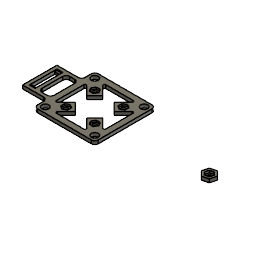
Assembly (1) (Autodesk Fusion 360 archive; units mm, degrees)
design "cam base (1)"
part number: 2026-03-15-12-51-07-522
Autodesk Fusion 360 part; units mm, degrees
sketch "Sketch1" plane through (0, 0, 0) normal (0, 1, 0) x (1, 0, 0)
  line L0 (26.5, -26.5) -> (-26.5, -26.5)
  line L1 (-26.5, -26.5) -> (-26.5, 26.5)
  line L2 (-26.5, 26.5) -> (26.5, 26.5)
  line L3 (26.5, 26.5) -> (26.5, -26.5)
  line L4 (26.5, -26.5) -> (-26.5, 26.5) construction
  line L5 (-26.5, -26.5) -> (26.5, 26.5) construction
  circle A0 centre (-21.5503, 21.5503) radius 3
  circle A1 centre (-21.5503, -21.5503) radius 3
  circle A2 centre (21.5503, -21.5503) radius 3
  circle A3 centre (21.5503, 21.5503) radius 3
  line L6 (-40, -12) -> (-45, -12)
  line L7 (-45, -12) -> (-45, 12)
  line L8 (-45, 12) -> (-40, 12)
  line L9 (-40, 12) -> (-40, -12)
  line L10 (-40, -12) -> (-45, 12) construction
  line L11 (-45, -12) -> (-40, 12) construction
  line L12 (-45, -10) -> (-40, -10)
  line L13 (-45, 10) -> (-40, 10)
  line L14 (17.9645, -17.9645) -> (21.5, -14.4289)
  line L15 (17.9645, 17.9645) -> (21.5, 14.4289)
  line L16 (21.5, 14.4289) -> (21.5, -14.4289)
  line L17 (21.5, -14.4289) -> (14.4289, -21.5)
  line L18 (21.5, 14.4289) -> (14.4289, 21.5)
  line L19 (-21.5, -14.4289) -> (-14.4289, -21.5)
  line L20 (-21.5, 14.4289) -> (-21.5, -14.4289)
  line L21 (-21.5, 14.4289) -> (-14.4289, 21.5)
  line L22 (14.4289, -21.5) -> (-14.4289, -21.5)
  line L23 (-14.4289, 21.5) -> (14.4289, 21.5)
  line L24 (-37, 15) -> (-37, -15)
  line L25 (-37, -15) -> (-48, -15)
  line L26 (-48, -15) -> (-48, 15)
  line L27 (-48, 15) -> (-37, 15)
  line L28 (-37, -15) -> (-26.5, -15)
  line L29 (-37, 15) -> (-26.5, 15)
  line L30 (-37, -12) -> (-26.5, -12)
  line L31 (-37, 12) -> (-26.5, 12)
  line L32 (-12.5, 12.5) -> (12.5, 12.5)
  line L33 (12.5, 12.5) -> (12.5, -12.5)
  line L34 (12.5, -12.5) -> (-12.5, -12.5)
  line L35 (-12.5, -12.5) -> (-12.5, 12.5)
  line L36 (-12.5, 12.5) -> (12.5, -12.5) construction
  line L37 (12.5, 12.5) -> (-12.5, -12.5) construction
  line L38 (9.499, 14.3011) -> (9.4397, 10.8016)
  line L39 (9.4397, 10.8016) -> (12.4407, 9.0005)
  line L40 (12.4407, 9.0005) -> (15.501, 10.6989)
  line L41 (15.501, 10.6989) -> (15.5603, 14.1984)
  line L42 (15.5603, 14.1984) -> (12.5593, 15.9995)
  line L43 (12.5593, 15.9995) -> (9.499, 14.3011)
  line L44 (-10.8016, 9.4397) -> (-9.0005, 12.4407)
  line L45 (-9.0005, 12.4407) -> (-10.6989, 15.501)
  line L46 (-10.6989, 15.501) -> (-14.1984, 15.5603)
  line L47 (-14.1984, 15.5603) -> (-15.9995, 12.5593)
  line L48 (-15.9995, 12.5593) -> (-14.3011, 9.499)
  line L49 (-14.3011, 9.499) -> (-10.8016, 9.4397)
  line L50 (-9.4397, -10.8016) -> (-12.4407, -9.0005)
  line L51 (-12.4407, -9.0005) -> (-15.501, -10.6989)
  line L52 (-15.501, -10.6989) -> (-15.5603, -14.1984)
  line L53 (-15.5603, -14.1984) -> (-12.5593, -15.9995)
  line L54 (-12.5593, -15.9995) -> (-9.499, -14.3011)
  line L55 (-9.499, -14.3011) -> (-9.4397, -10.8016)
  line L56 (10.8016, -9.4397) -> (9.0005, -12.4407)
  line L57 (9.0005, -12.4407) -> (10.6989, -15.501)
  line L58 (10.6989, -15.501) -> (14.1984, -15.5603)
  line L59 (14.1984, -15.5603) -> (15.9995, -12.5593)
  line L60 (15.9995, -12.5593) -> (14.3011, -9.499)
  line L61 (14.3011, -9.499) -> (10.8016, -9.4397)
  circle A4 centre (12.5, 12.5) radius 1.75
  circle A5 centre (-12.5, 12.5) radius 1.75
  circle A6 centre (-12.5, -12.5) radius 1.75
  circle A7 centre (12.5, -12.5) radius 1.75
  line L62 (21.5, 14.4289) -> (11.9541, 4.883)
  line L63 (14.4289, 21.5) -> (4.883, 11.9541)
  line L64 (4.883, 11.9541) -> (11.9541, 4.883)
  line L65 (-21.5, 14.4289) -> (-11.9541, 4.883)
  line L66 (-11.9541, 4.883) -> (-4.883, 11.9541)
  line L67 (-14.4289, 21.5) -> (-4.883, 11.9541)
  line L68 (-14.4289, -21.5) -> (-4.883, -11.9541)
  line L69 (-4.883, -11.9541) -> (-11.9541, -4.883)
  line L70 (-21.5, -14.4289) -> (-11.9541, -4.883)
  line L71 (21.5, -14.4289) -> (11.9541, -4.883)
  line L72 (11.9541, -4.883) -> (4.883, -11.9541)
  line L73 (14.4289, -21.5) -> (4.883, -11.9541)
  point P0 (-42.5, 0)
  point P1 (-42.5, 0)
  point P2 (12.5, 12.5)
  dimension "d1" = 53
  dimension "d2" = 53
  dimension "d3" = 6
  dimension "d5" = 360
  dimension "d8" = 5
  dimension "d9" = 24
  dimension "d11" = 2
  dimension "d12" = 2
  dimension "d20" = 7
  dimension "d21" = 5
  dimension "d22" = 5
  dimension "d24" = 5
  dimension "d27" = 10
  dimension "d33" = 5
  dimension "d34" = 5
  dimension "d35" = 5
  dimension "d39" = 5
  dimension "d40" = 5
  dimension "d41" = 5
  dimension "d42" = 10
  dimension "d43" = 10
  dimension "d44" = 40
  dimension "d47" = -3
  dimension "d54" = 25
  dimension "d55" = 25
  dimension "d56" = 3.5
  dimension "d58" = 360
  dimension "d59" = 3.5
  dimension "d61" = 360
  dimension "d69" = 13.5
  dimension "d70" = 13.5
  dimension "d72" = 360
  constraint horizontal L0
  constraint perpendicular L0 L1
  constraint parallel L0 L2
  constraint parallel L1 L3
  constraint coincident L4 origin
  constraint coincident L5 origin
  constraint coincident L4 A0.centre
  constraint horizontal L6
  constraint perpendicular L6 L7
  constraint parallel L6 L8
  constraint parallel L7 L9
  constraint coincident L10 P1
  constraint coincident L11 P1
  constraint coincident P1 P0
  constraint coincident L7 L12.start
  constraint coincident L9 L12.end
  constraint perpendicular L9 L12
  constraint coincident L7 L13.start
  constraint coincident L9 L13.end
  constraint perpendicular L9 L13
  constraint perpendicular L4 L14
  constraint perpendicular L5 L15
  constraint perpendicular L4 L17
  constraint perpendicular L5 L18
  constraint horizontal L22
  constraint parallel L22 L23
  constraint coincident L1 L28.end
  constraint perpendicular L1 L28
  constraint coincident L1 L29.end
  constraint perpendicular L1 L29
  constraint coincident L24 L30.start
  constraint coincident L1 L30.end
  constraint perpendicular L1 L30
  constraint coincident L24 L31.start
  constraint coincident L1 L31.end
  constraint perpendicular L1 L31
  constraint horizontal L32
  constraint perpendicular L32 L33
  constraint parallel L32 L34
  constraint parallel L33 L35
  constraint coincident L36 origin
  constraint coincident L37 origin
  constraint coincident P2 L32.end
  constraint perpendicular L18 L62
  constraint perpendicular L18 L63
  measures "d1" distance of L1.end L2.end
  measures "d2" distance of L0.end L1.end
  measures "d3" diameter of A0
  measures "d8" distance of L7.end L8.end
  measures "d9" distance of L6.end L7.end
  measures "d11" distance of L6 L12
  measures "d12" distance of L8 L13
  measures "d20" distance of L1.end A0.centre
  measures "d21" distance of L14.start L14.end
  measures "d22" distance of L15.start L15.end
  measures "d24" distance of L3 L16
  measures "d27" distance of L15.end L18.end
  measures "d33" distance of L1 L20
  measures "d34" distance of L0 L22
  measures "d35" distance of L2 L23
  measures "d39" distance of L4 L17.end
  measures "d40" distance of L5 L19.end
  measures "d41" distance of L4 L21.end
  measures "d42" distance of L20.start L21.end
  measures "d43" distance of L19.end L19.start
  measures "d44" distance of origin L9
  measures "d54" distance of L33.end L34.end
  measures "d55" distance of P2 L33.end
  measures "d56" distance of L38.start P2
  measures "d59" diameter of A4
  measures "d69" distance of L15.end L62.end
  measures "d70" distance of L18.end L63.end
extrude "Extrude1" add sketch "Sketch1" along normal blind 3 contours L0 L1 L2 L3 | L1 L24 L28 L30 | L24 L25 L26 L27 | L1 L24 L29 L31 | L14 L17 L33 L34 L57 L58 L59 L60 L61 L71 L73 | L15 L18 L32 L33 L38 L40 L41 L42 L43 L62 L63 | L33 L34 L56 L57 L61 L71 L72 L73 | L19 L34 L35 L51 L52 L53 L54 L55 L68 L70 | L32 L33 L38 L39 L40 L62 L63 L64 | L34 L35 L50 L51 L55 L68 L69 L70 | L21 L32 L35 L45 L46 L47 L48 L49 L65 L67 | L32 L35 L44 L45 L49 L65 L66 L67 makes body 1
extrude "Extrude2" add sketch "Sketch1" along normal blind 2 separate body contours L6 L7 L9 L12 | L7 L8 L9 L13 makes body 2 at (-41.6667, 0.6667, 12) makes body 3 at (-41.6667, 0, -10.6667)
combine "Combine1" operation add target body 1 tool bodies 3 2
fillet "Fillet2" radius 3 4 edges at (-37, 1.5, 12) (-37, 1.5, -12) (-26.5, 1.5, 12) (-26.5, 1.5, -12) on bodies 1
fillet "Fillet3" radius 3 2 edges at (-26.5, 1.5, -15) (-26.5, 1.5, 15) on bodies 1
extrude "Extrude5" add sketch "Sketch1" along normal blind 1.5 contours L33 L34 L57 L58 L59 L60 L61 A7 | L33 L34 L56 L57 L61 A7 | L32 L33 L38 L39 L40 A4 | L32 L33 L38 L40 L41 L42 L43 A4 | L34 L35 L51 L52 L53 L54 L55 A6 | L34 L35 L50 L51 L55 A6 | L32 L35 L45 L46 L47 L48 L49 A5 | L32 L35 L44 L45 L49 A5 bodies 1
sketch "Sketch2" plane through (0, 0, 0) normal (0, 1, 0) x (1, 0, 0)
  line L0 (97.8787, 2.1213) -> (96.9728, -1.2594)
  line L1 (96.9728, -1.2594) -> (99.4477, -3.7343)
  line L2 (99.4477, -3.7343) -> (102.8284, -2.8284)
  line L3 (102.8284, -2.8284) -> (103.7343, 0.5523)
  line L4 (103.7343, 0.5523) -> (101.2594, 3.0272)
  line L5 (101.2594, 3.0272) -> (97.8787, 2.1213)
  line L6 (104.4614, -4.4614) -> (105.965, 1.15)
  line L7 (105.965, 1.15) -> (101.8571, 5.2579)
  line L8 (101.8571, 5.2579) -> (96.2457, 3.7543)
  line L9 (96.2457, 3.7543) -> (94.7421, -1.8571)
  line L10 (94.7421, -1.8571) -> (98.85, -5.965)
  line L11 (98.85, -5.965) -> (104.4614, -4.4614)
  circle A0 centre (100.3536, -0.3536) radius 1.5
  point P0 (100.3536, -0.3536)
  dimension "d62" = 3.5
  dimension "d63" = 2
  dimension "d64" = 3
  constraint coincident P0 A0.centre
  measures "d62" distance of L0.start P0
  measures "d64" diameter of A0
extrude "Extrude3" add sketch "Sketch2" along normal blind 3 separate body contours L6 L7 L8 L9 L10 L11 makes body 4
extrude "Extrude4" add sketch "Sketch2" along normal blind 1 contours L0 L1 L2 L3 L4 L5 bodies 4
fillet "Fillet5" radius 1 8 edges at (21.5, 1.5, 14.4289) (14.4289, 1.5, 21.5) (-14.4289, 1.5, -21.5) (-21.5, 1.5, -14.4289) (14.4289, 1.5, -21.5) (21.5, 1.5, -14.4289) (-21.5, 1.5, 14.4289) (-14.4289, 1.5, 21.5) on bodies 1
fillet "Fillet6" radius 3 4 edges at (26.5, 1.5, -26.5) (-26.5, 1.5, -26.5) (-26.5, 1.5, 26.5) (26.5, 1.5, 26.5) on bodies 1
